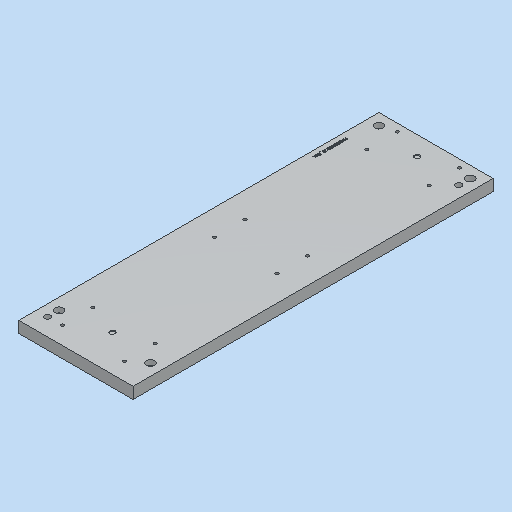
# Autodesk Inventor part: MM0948AN120_G01_109
Saved by Autodesk Inventor 2023.3 (Build 273359000, 359)
## iProperties
Part Number: MM0948AN120_G01_109
Material: 3.3547 AlMg4,5Mn0,7 - AW 5083
Description: =<RBPARTNOTITLE2>
Document SubType Name: Modeling
Designer: ric7an
Mass: 2852.53 g
Surface Area: 1646.02 cm^2
Volume: 1056.49 cm^3
Density: 2.7 g/cm^3
Appearance: Aluminium AnP
Created: 2023-03-23
RBDOCUMENTTYPE: DRF
RBDOCUMENTVERSION: 00
RBDRAWINGMAINSCALE: 1:1
RBDRAWINGMISSINGSPEC: --
RBDRAWINGVOLUME: --
RBGBEDGESIN1: +0,5
RBGBEDGESIN2: +0,2
RBGBEDGESOUT1: -0,3
RBGBEDGESOUT2: -0,1
RBMATERIAL: =<Material>
RBMATMEETS: --
RBMATNO: =<Part Number>
RBPARTMADEOF: 15 x 473 x 150 (FM)
RBPARTNO: SIEHE MNR
RBPARTNOTITLE1: manufactured part
RBPARTNOTITLE2: Anfertigungsteil
RBPARTSAFETYINDICATOR: --
RBSURFACE: anodised colourless
RBSURFACE2: eloxiert farblos
RBZEDGESNORM: ISO13715:2002-06
RBZGENDIMCLASS: m
RBZGENDIMNORM: ISO 2768-1:1989-11
RBZGENGEOCLASS: H
RBZGENGEONORM: ISO 2768-2:1989-11
RBZSURFACENORM: ISO13D2:2002-02
RBZTOLERANCENORM: ISO 14405-1:2010-12
AnP_Material: =<Material>
AnP_TemplVers: 20190222
AnP_Kategorie: 1
MaxAbmaße: 15 x 473 x 150 (FM)
AnP_Kommentar_aktuell: =<Comments>
AnP_Material_aktuell: =<Material>
Author: FH/Wi
Keywords: =<RBPARTMADEOF>
Comments: =<RBSURFACE2>
Revision Number: 01
Autodesk Inventor part; units mm, degrees
ref_plane "YZ Plane" through (0, 0, 0) normal (1, 0, 0) x (0, 1, 0)
ref_plane "XZ Plane" through (0, 0, 0) normal (0, 1, 0) x (-1, 0, 0)
ref_plane "XY Plane" through (0, 0, 0) normal (0, 0, 1) x (1, 0, 0)
sketch "Skizze1" plane through (0, 0, 0) normal (0, 0, 1) x (1, 0, 0)
  line L0 (-75, 236.5) -> (75, 236.5)
  line L1 (75, 236.5) -> (75, -236.5)
  line L2 (75, -236.5) -> (-75, -236.5)
  line L3 (-75, -236.5) -> (-75, 236.5)
  line L4 (0, 381.5) -> (0, -364) projected
  line L5 (-105, 0) -> (105, 0) projected
  point P0 (0, 0)
  dimension "d0" = 473
  dimension "d1" = 150
  constraints: 8 end point, 2 parallel, 1 horizontal, 1 perpendicular, 2 other
  measures "d0" distance of L0.end L1.end
  measures "d1" distance of L0.start L0.end
extrude "Extrusion1" add sketch "Skizze1" along normal blind 15
sketch "Skizze12" plane through (0, 0, 15) normal (0, 0, 1) x (1, 0, 0)
  line L0 (75, 236.5) -> (-75, 236.5) projected
  line L1 (-75, 236.5) -> (-75, -236.5) projected
  line L2 (75, -236.5) -> (75, 236.5) projected
  line L3 (-75, 236.5) -> (75, 236.5)
  line L4 (75, 236.5) -> (75, 156.5)
  line L5 (75, 156.5) -> (-75, 156.5)
  line L6 (-75, 156.5) -> (-75, 236.5)
  point P0 (0, 0)
  dimension "d107" = 80
  constraints: 8 end point, 2 parallel, 1 horizontal, 1 perpendicular, 1 point on line
  measures "d107" distance between parallel lines of L5 L0
sketch "Skizze2" plane through (0, 0, 15) normal (0, 0, 1) x (1, 0, 0)
  line L0 (0, 381.5) -> (0, -364) projected
  line L1 (-105, 0) -> (105, 0) projected
  line L2 (75, 236.5) -> (-75, 236.5) projected
  line L3 (-75, -236.5) -> (75, -236.5) projected
  point P0 (0, 0)
  point P1 (0, 211.5)
  point P2 (0, -188.5)
  dimension "d4" = 400
  dimension "d129" = 25
  dimension "d130" = 48
  constraints: 2 point on line
  measures "d4" distance of point (0, -188.5) point (0, 211.5)
  measures "d129" distance from line of point (0, 211.5) L2
  measures "d130" distance from line of L3 point (0, -188.5)
hole "Bohrung1" at (0, 211.5, 15) at (0, -188.5, 15) direction (0, 0, -1) diameter 7 depth 1.6
sketch "Skizze3" plane through (0, 0, 15) normal (0, 0, 1) x (1, 0, 0)
  line L0 (0, 381.5) -> (0, -364) projected
  line L1 (-105, 0) -> (105, 0) projected
  line L2 (75, 236.5) -> (-75, 236.5) projected
  point P0 (0, 0)
  point P1 (-41, 226.5)
  point P2 (-41, 186.5)
  point P3 (41, 226.5)
  point P4 (41, 186.5)
  dimension "d12" = 40
  dimension "d13" = 82
  dimension "d14" = 10
  constraints: 2 symmetric about line, 1 vertical alignment
  measures "d12" distance of point (41, 226.5) point (41, 186.5)
  measures "d13" distance of point (41, 226.5) point (-41, 226.5)
  measures "d14" distance from line of L2 point (-41, 226.5)
hole "Bohrung2" at (-41, 226.5, 15) at (-41, 186.5, 15) at (41, 226.5, 15) at (41, 186.5, 15) direction (0, 0, -1) diameter 4.134 end through all thread size "M5x0.8" designation "M5" class "6H" standard "ISO Metric profile"
pattern_linear "Rechteckige Anordnung1" count 3 spacing 200 along (0, -1, 0) of "Bohrung2"
sketch "Skizze6" plane through (0, 0, 15) normal (0, 0, -1) x (-1, 0, 0)
  line L0 (0, -364) -> (0, 381.5) projected
  line L1 (-105, 0) -> (105, 0) projected
  line L2 (75, 236.5) -> (-75, 236.5) projected
  line L3 (75, -236.5) -> (-75, -236.5) projected
  point P0 (0, 0)
  point P1 (-60, 221.5)
  point P2 (60, 221.5)
  point P3 (-60, -198.5)
  point P4 (60, -198.5)
  dimension "d48" = 120
  dimension "d85" = 420
  dimension "d86" = 120
  dimension "d104" = 38
  constraints: 2 symmetric about line, 1 horizontal alignment
  measures "d48" distance of point (60, 221.5) point (-60, 221.5)
  measures "d85" vertical distance of point (-60, -198.5) point (60, 221.5)
  measures "d86" distance of point (60, -198.5) point (-60, -198.5)
  measures "d104" distance from line of L3 point (-60, -198.5)
hole "Bohrung5" at (60, -198.5, 15) at (-60, -198.5, 15) at (60, 221.5, 15) at (-60, 221.5, 15) direction (0, 0, -1) diameter 6.6 end through all counterbore diameter 11 counterbore depth 6.8 clearance for "Inbusschraube ISO 4762  versenkt" size "M6" standard "ISO"
sketch "Skizze10" plane through (0, 0, 15) normal (0, 0, 1) x (1, 0, 0)
  circle A0 centre (-60, -198.5) radius 5.5 projected
  line L0 (-105, 0) -> (105, 0) projected
  line L1 (0, 381.5) -> (0, -364) projected
  circle A1 centre (-60, 221.5) radius 5.5 projected
  circle A2 centre (60, 221.5) radius 3.3 projected
  point P0 (0, 0)
  point P1 (-60, -213.5)
  point P2 (60, 206.5)
  dimension "d106" = 15
  dimension "d128" = 15
  constraints: 2 vertical alignment
  measures "d106" distance of point (-60, -213.5) A0.centre
  measures "d128" distance of point (60, 206.5) A2.centre
hole "Bohrung8" at (-60, -213.5, 15) at (60, 206.5, 15) direction (0, 0, -1) diameter 8 end through all
sketch "Skizze15" plane through (0, 0, 15) normal (0, 0, 1) x (1, 0, 0)
  line L0 (-65, 186.5) -> (-65, 138.8519) construction
  line L1 (-65, 138.8519) -> (-74.8862, 138.8519) construction
  line L2 (-74.8862, 138.8519) -> (-74.8862, 186.5) construction
  line L3 (-74.8862, 186.5) -> (-65, 186.5) construction
  line L4 (-75, 236.5) -> (-75, -236.5) projected
  line L5 (75, 236.5) -> (-75, 236.5) projected
  line L6 (-68.5794, 183.1447) -> (-68.5794, 183.6098)
  line L7 (-68.5794, 183.6098) -> (-65.5644, 183.6098)
  line L8 (-65.5644, 183.6098) -> (-67.6151, 184.5231)
  line L9 (-67.6151, 184.5231) -> (-67.6151, 184.8067)
  line L10 (-67.6151, 184.8067) -> (-65.5644, 185.7115)
  line L11 (-65.5644, 185.7115) -> (-68.5794, 185.7115)
  line L12 (-68.5794, 185.7115) -> (-68.5794, 186.1455)
  line L13 (-68.5794, 186.1455) -> (-65.0794, 186.1455)
  line L14 (-65.0794, 186.1455) -> (-65.0794, 185.5101)
  line L15 (-65.0794, 185.5101) -> (-67.028, 184.6365)
  line L16 (-67.028, 184.6365) -> (-65.0794, 183.7913)
  line L17 (-65.0794, 183.7913) -> (-65.0794, 183.1447)
  line L18 (-65.0794, 183.1447) -> (-68.5794, 183.1447)
  line L19 (-68.5794, 179.4348) -> (-68.5794, 179.8999)
  line L20 (-68.5794, 179.8999) -> (-65.5644, 179.8999)
  line L21 (-65.5644, 179.8999) -> (-67.6151, 180.8132)
  line L22 (-67.6151, 180.8132) -> (-67.6151, 181.0968)
  line L23 (-67.6151, 181.0968) -> (-65.5644, 182.0016)
  line L24 (-65.5644, 182.0016) -> (-68.5794, 182.0016)
  line L25 (-68.5794, 182.0016) -> (-68.5794, 182.4356)
  line L26 (-68.5794, 182.4356) -> (-65.0794, 182.4356)
  line L27 (-65.0794, 182.4356) -> (-65.0794, 181.8002)
  line L28 (-65.0794, 181.8002) -> (-67.028, 180.9267)
  line L29 (-67.028, 180.9267) -> (-65.0794, 180.0814)
  line L30 (-65.0794, 180.0814) -> (-65.0794, 179.4348)
  line L31 (-65.0794, 179.4348) -> (-68.5794, 179.4348)
  spline S0 degree 2 poles (-66.8294, 176.6467) (-67.7711, 176.6467) (-68.6532, 177.1941) (-68.6532, 177.7642) knots 0 0 0 1 2 2 2
  spline S1 degree 2 poles (-68.6532, 177.7642) (-68.6532, 178.3428) (-67.7541, 178.8845) (-66.8323, 178.8845) knots 0 0 0 1 2 2 2
  spline S2 degree 2 poles (-66.8323, 178.8845) (-65.8849, 178.8845) (-65.0085, 178.3371) (-65.0085, 177.7642) knots 0 0 0 1 2 2 2
  spline S3 degree 2 poles (-65.0085, 177.7642) (-65.0085, 177.1884) (-65.9161, 176.6467) (-66.8294, 176.6467) knots 0 0 0 1 2 2 2
  spline S4 degree 2 poles (-67.8959, 177.248) (-67.7229, 177.1799) (-67.1896, 177.1232) (-66.8294, 177.1232) knots 0 0 0 1 2 2 2
  spline S5 degree 2 poles (-66.8294, 177.1232) (-66.4692, 177.1232) (-65.9388, 177.1799) (-65.7601, 177.2508) knots 0 0 0 1 2 2 2
  spline S6 degree 2 poles (-65.7601, 177.2508) (-65.5814, 177.3217) (-65.3971, 177.5685) (-65.3971, 177.7642) knots 0 0 0 1 2 2 2
  spline S7 degree 2 poles (-65.3971, 177.7642) (-65.3971, 177.9599) (-65.5814, 178.2123) (-65.7658, 178.2861) knots 0 0 0 1 2 2 2
  spline S8 degree 2 poles (-65.7658, 178.2861) (-65.9445, 178.357) (-66.4891, 178.408) (-66.8323, 178.408) knots 0 0 0 1 2 2 2
  spline S9 degree 2 poles (-66.8323, 178.408) (-67.201, 178.408) (-67.6945, 178.3626) (-67.8874, 178.2889) knots 0 0 0 1 2 2 2
  spline S10 degree 2 poles (-67.8874, 178.2889) (-68.0689, 178.2208) (-68.2646, 177.9684) (-68.2646, 177.7642) knots 0 0 0 1 2 2 2
  spline S11 degree 2 poles (-68.2646, 177.7642) (-68.2646, 177.5713) (-68.0802, 177.3189) (-67.8959, 177.248) knots 0 0 0 1 2 2 2
  spline S12 degree 2 poles (-66.2168, 176.295) (-65.9473, 176.295) (-65.4992, 176.1191) (-65.3375, 175.966) knots 0 0 0 1 2 2 2
  spline S13 degree 2 poles (-65.3375, 175.966) (-65.1815, 175.8213) (-65.0085, 175.3987) (-65.0085, 175.1831) knots 0 0 0 1 2 2 2
  spline S14 degree 2 poles (-65.0085, 175.1831) (-65.0085, 174.9421) (-65.1702, 174.5506) (-65.3233, 174.406) knots 0 0 0 1 2 2 2
  spline S15 degree 2 poles (-65.3233, 174.406) (-65.5162, 174.2245) (-66.1402, 174.0259) (-66.6195, 174.0259) knots 0 0 0 1 2 2 2
  spline S16 degree 2 poles (-66.6195, 174.0259) (-67.0535, 174.0259) (-67.8306, 174.2216) (-68.0887, 174.4117) knots 0 0 0 1 2 2 2
  spline S17 degree 2 poles (-68.0887, 174.4117) (-68.361, 174.613) (-68.6475, 175.1803) (-68.6475, 175.5944) knots 0 0 0 1 2 2 2
  spline S18 degree 2 poles (-68.6475, 175.5944) (-68.6475, 175.688) (-68.6276, 175.9007) (-68.5993, 175.9915) knots 0 0 0 1 2 2 2
  line L32 (-68.5993, 175.9915) -> (-68.1483, 175.9915)
  line L33 (-68.1483, 175.9915) -> (-68.1483, 175.9688)
  spline S19 degree 2 poles (-68.1483, 175.9688) (-68.1823, 175.9092) (-68.2419, 175.6596) (-68.2419, 175.532) knots 0 0 0 1 2 2 2
  spline S20 degree 2 poles (-68.2419, 175.532) (-68.2419, 175.0725) (-67.6349, 174.5478) (-67.0733, 174.5109) knots 0 0 0 1 2 2 2
  spline S21 degree 2 poles (-67.0733, 174.5109) (-67.201, 174.6981) (-67.3173, 175.0385) (-67.3173, 175.2399) knots 0 0 0 1 2 2 2
  spline S22 degree 2 poles (-67.3173, 175.2399) (-67.3173, 175.4327) (-67.2322, 175.7532) (-67.1102, 175.9149) knots 0 0 0 1 2 2 2
  spline S23 degree 2 poles (-67.1102, 175.9149) (-66.9656, 176.1021) (-66.5259, 176.295) (-66.2168, 176.295) knots 0 0 0 1 2 2 2
  spline S24 degree 2 poles (-66.5146, 174.4996) (-66.16, 174.4996) (-65.7119, 174.6301) (-65.59, 174.7464) knots 0 0 0 1 2 2 2
  spline S25 degree 2 poles (-65.59, 174.7464) (-65.4765, 174.8485) (-65.3914, 175.0612) (-65.3914, 175.186) knots 0 0 0 1 2 2 2
  spline S26 degree 2 poles (-65.3914, 175.186) (-65.3914, 175.4753) (-65.8055, 175.8185) (-66.1969, 175.8185) knots 0 0 0 1 2 2 2
  spline S27 degree 2 poles (-66.1969, 175.8185) (-66.4182, 175.8185) (-66.7046, 175.705) (-66.8067, 175.5802) knots 0 0 0 1 2 2 2
  spline S28 degree 2 poles (-66.8067, 175.5802) (-66.8805, 175.4895) (-66.9287, 175.2654) (-66.9287, 175.1349) knots 0 0 0 1 2 2 2
  spline S29 degree 2 poles (-66.9287, 175.1349) (-66.9287, 174.9846) (-66.8237, 174.6386) (-66.7358, 174.5081) knots 0 0 0 1 2 2 2
  spline S30 degree 2 poles (-66.7358, 174.5081) (-66.7018, 174.5053) (-66.5855, 174.4996) (-66.5146, 174.4996) knots 0 0 0 1 2 2 2
  line L34 (-67.3768, 171.3201) -> (-67.3768, 171.737)
  line L35 (-67.3768, 171.737) -> (-68.5794, 171.737)
  line L36 (-68.5794, 171.737) -> (-68.5794, 172.188)
  line L37 (-68.5794, 172.188) -> (-67.3768, 172.188)
  line L38 (-67.3768, 172.188) -> (-67.3768, 173.7338)
  line L39 (-67.3768, 173.7338) -> (-66.8833, 173.7338)
  line L40 (-66.8833, 173.7338) -> (-65.0794, 172.1682)
  line L41 (-65.0794, 172.1682) -> (-65.0794, 171.737)
  line L42 (-65.0794, 171.737) -> (-66.9996, 171.737)
  line L43 (-66.9996, 171.737) -> (-66.9996, 171.3201)
  line L44 (-66.9996, 171.3201) -> (-67.3768, 171.3201)
  line L45 (-66.9996, 172.188) -> (-65.6325, 172.188)
  line L46 (-65.6325, 172.188) -> (-66.9996, 173.3651)
  line L47 (-66.9996, 173.3651) -> (-66.9996, 172.188)
  spline S31 degree 2 poles (-68.6588, 169.8878) (-68.6588, 170.1487) (-68.5028, 170.577) (-68.3582, 170.7273) knots 0 0 0 1 2 2 2
  spline S32 degree 2 poles (-68.3582, 170.7273) (-68.2164, 170.8748) (-67.8306, 171.028) (-67.6122, 171.028) knots 0 0 0 1 2 2 2
  spline S33 degree 2 poles (-67.6122, 171.028) (-67.3286, 171.028) (-66.8521, 170.7245) (-66.7103, 170.4352) knots 0 0 0 1 2 2 2
  line L48 (-66.7103, 170.4352) -> (-66.6961, 170.4352)
  spline S34 degree 2 poles (-66.6961, 170.4352) (-66.5458, 170.6933) (-66.1884, 170.9429) (-65.9218, 170.9429) knots 0 0 0 1 2 2 2
  spline S35 degree 2 poles (-65.9218, 170.9429) (-65.5276, 170.9429) (-65, 170.3472) (-65, 169.8878) knots 0 0 0 1 2 2 2
  spline S36 degree 2 poles (-65, 169.8878) (-65, 169.4113) (-65.4992, 168.8355) (-65.8906, 168.8355) knots 0 0 0 1 2 2 2
  spline S37 degree 2 poles (-65.8906, 168.8355) (-66.126, 168.8355) (-66.5855, 169.1106) (-66.716, 169.3687) knots 0 0 0 1 2 2 2
  line L49 (-66.716, 169.3687) -> (-66.7301, 169.3687)
  spline S38 degree 2 poles (-66.7301, 169.3687) (-66.872, 169.0624) (-67.2804, 168.7476) (-67.6037, 168.7476) knots 0 0 0 1 2 2 2
  spline S39 degree 2 poles (-67.6037, 168.7476) (-68.0519, 168.7476) (-68.6588, 169.3999) (-68.6588, 169.8878) knots 0 0 0 1 2 2 2
  spline S40 degree 2 poles (-67.6491, 169.2297) (-67.4335, 169.2297) (-67.1783, 169.3999) (-67.0478, 169.641) knots 0 0 0 1 2 2 2
  spline S41 degree 2 poles (-67.0478, 169.641) (-67.0024, 169.7204) (-66.8975, 169.987) (-66.8294, 170.1544) knots 0 0 0 1 2 2 2
  spline S42 degree 2 poles (-66.8294, 170.1544) (-66.9571, 170.3472) (-67.3371, 170.5543) (-67.5782, 170.5543) knots 0 0 0 1 2 2 2
  spline S43 degree 2 poles (-67.5782, 170.5543) (-67.8959, 170.5543) (-68.31, 170.1714) (-68.31, 169.8821) knots 0 0 0 1 2 2 2
  spline S44 degree 2 poles (-68.31, 169.8821) (-68.31, 169.5871) (-67.9554, 169.2297) (-67.6491, 169.2297) knots 0 0 0 1 2 2 2
  spline S45 degree 2 poles (-65.8963, 169.295) (-65.6609, 169.295) (-65.346, 169.6098) (-65.346, 169.8906) knots 0 0 0 1 2 2 2
  spline S46 degree 2 poles (-65.346, 169.8906) (-65.346, 170.1459) (-65.6268, 170.472) (-65.8679, 170.472) knots 0 0 0 1 2 2 2
  spline S47 degree 2 poles (-65.8679, 170.472) (-66.0409, 170.472) (-66.282, 170.3047) (-66.3784, 170.1374) knots 0 0 0 1 2 2 2
  spline S48 degree 2 poles (-66.3784, 170.1374) (-66.4182, 170.0665) (-66.5571, 169.7658) (-66.5968, 169.6438) knots 0 0 0 1 2 2 2
  spline S49 degree 2 poles (-66.5968, 169.6438) (-66.4408, 169.4396) (-66.109, 169.295) (-65.8963, 169.295) knots 0 0 0 1 2 2 2
  line L50 (-68.5794, 168.5972) -> (-65.0794, 167.4173)
  line L51 (-65.0794, 167.4173) -> (-65.0794, 166.8444)
  line L52 (-65.0794, 166.8444) -> (-68.5794, 165.6645)
  line L53 (-68.5794, 165.6645) -> (-68.5794, 166.1552)
  line L54 (-68.5794, 166.1552) -> (-67.6009, 166.4729)
  line L55 (-67.6009, 166.4729) -> (-67.6009, 167.8088)
  line L56 (-67.6009, 167.8088) -> (-68.5794, 168.1264)
  line L57 (-68.5794, 168.1264) -> (-68.5794, 168.5972)
  line L58 (-67.2038, 166.6005) -> (-65.5559, 167.1422)
  line L59 (-65.5559, 167.1422) -> (-67.2038, 167.6811)
  line L60 (-67.2038, 167.6811) -> (-67.2038, 166.6005)
  line L61 (-68.5794, 162.8282) -> (-68.5794, 163.3501)
  line L62 (-68.5794, 163.3501) -> (-65.5616, 164.8987)
  line L63 (-65.5616, 164.8987) -> (-68.5794, 164.8987)
  line L64 (-68.5794, 164.8987) -> (-68.5794, 165.3327)
  line L65 (-68.5794, 165.3327) -> (-65.0794, 165.3327)
  line L66 (-65.0794, 165.3327) -> (-65.0794, 164.6718)
  line L67 (-65.0794, 164.6718) -> (-67.8505, 163.2622)
  line L68 (-67.8505, 163.2622) -> (-65.0794, 163.2622)
  line L69 (-65.0794, 163.2622) -> (-65.0794, 162.8282)
  line L70 (-65.0794, 162.8282) -> (-68.5794, 162.8282)
  line L71 (-68.5794, 160.2358) -> (-68.5794, 161.9433)
  line L72 (-68.5794, 161.9433) -> (-68.222, 161.9433)
  line L73 (-68.222, 161.9433) -> (-68.222, 161.3079)
  line L74 (-68.222, 161.3079) -> (-65.8764, 161.3079)
  line L75 (-65.8764, 161.3079) -> (-65.8764, 161.9433)
  line L76 (-65.8764, 161.9433) -> (-65.5559, 161.9433)
  spline S50 degree 2 poles (-65.5559, 161.9433) (-65.5559, 161.5831) (-65.3517, 161.2427) (-65.0681, 161.22) knots 0 0 0 1 2 2 2
  line L77 (-65.0681, 161.22) -> (-65.0681, 160.857)
  line L78 (-65.0681, 160.857) -> (-68.222, 160.857)
  line L79 (-68.222, 160.857) -> (-68.222, 160.2358)
  line L80 (-68.222, 160.2358) -> (-68.5794, 160.2358)
  line L81 (-68.5794, 157.4335) -> (-68.5794, 159.592)
  line L82 (-68.5794, 159.592) -> (-68.0831, 159.592)
  spline S51 degree 2 poles (-68.0831, 159.592) (-67.8647, 159.3594) (-67.4591, 158.9453) (-67.2407, 158.7468) knots 0 0 0 1 2 2 2
  spline S52 degree 2 poles (-67.2407, 158.7468) (-66.8011, 158.3468) (-66.2735, 158.0547) (-65.9927, 158.0547) knots 0 0 0 1 2 2 2
  spline S53 degree 2 poles (-65.9927, 158.0547) (-65.8452, 158.0547) (-65.624, 158.1455) (-65.5531, 158.2277) knots 0 0 0 1 2 2 2
  spline S54 degree 2 poles (-65.5531, 158.2277) (-65.4822, 158.31) (-65.4113, 158.5255) (-65.4113, 158.656) knots 0 0 0 1 2 2 2
  spline S55 degree 2 poles (-65.4113, 158.656) (-65.4113, 158.7808) (-65.4737, 159.0361) (-65.5219, 159.1524) knots 0 0 0 1 2 2 2
  spline S56 degree 2 poles (-65.5219, 159.1524) (-65.5616, 159.2516) (-65.675, 159.436) (-65.7147, 159.4927) knots 0 0 0 1 2 2 2
  line L83 (-65.7147, 159.4927) -> (-65.7147, 159.5182)
  line L84 (-65.7147, 159.5182) -> (-65.2156, 159.5182)
  spline S57 degree 2 poles (-65.2156, 159.5182) (-65.1447, 159.3736) (-65.0057, 158.8545) (-65.0057, 158.622) knots 0 0 0 1 2 2 2
  spline S58 degree 2 poles (-65.0057, 158.622) (-65.0057, 158.1313) (-65.5247, 157.5782) (-65.9672, 157.5782) knots 0 0 0 1 2 2 2
  spline S59 degree 2 poles (-65.9672, 157.5782) (-66.1742, 157.5782) (-66.5203, 157.6746) (-66.6677, 157.7597) knots 0 0 0 1 2 2 2
  spline S60 degree 2 poles (-66.6677, 157.7597) (-66.8209, 157.8448) (-67.1216, 158.0916) (-67.2662, 158.2277) knots 0 0 0 1 2 2 2
  spline S61 degree 2 poles (-67.2662, 158.2277) (-67.5073, 158.4489) (-68.0235, 158.9907) (-68.1738, 159.1524) knots 0 0 0 1 2 2 2
  line L85 (-68.1738, 159.1524) -> (-68.1738, 157.4335)
  line L86 (-68.1738, 157.4335) -> (-68.5794, 157.4335)
  spline S62 degree 2 poles (-66.8294, 154.7873) (-67.7711, 154.7873) (-68.6532, 155.3347) (-68.6532, 155.9048) knots 0 0 0 1 2 2 2
  spline S63 degree 2 poles (-68.6532, 155.9048) (-68.6532, 156.4834) (-67.7541, 157.0251) (-66.8323, 157.0251) knots 0 0 0 1 2 2 2
  spline S64 degree 2 poles (-66.8323, 157.0251) (-65.8849, 157.0251) (-65.0085, 156.4777) (-65.0085, 155.9048) knots 0 0 0 1 2 2 2
  spline S65 degree 2 poles (-65.0085, 155.9048) (-65.0085, 155.329) (-65.9161, 154.7873) (-66.8294, 154.7873) knots 0 0 0 1 2 2 2
  spline S66 degree 2 poles (-67.8959, 155.3886) (-67.7229, 155.3205) (-67.1896, 155.2638) (-66.8294, 155.2638) knots 0 0 0 1 2 2 2
  spline S67 degree 2 poles (-66.8294, 155.2638) (-66.4692, 155.2638) (-65.9388, 155.3205) (-65.7601, 155.3914) knots 0 0 0 1 2 2 2
  spline S68 degree 2 poles (-65.7601, 155.3914) (-65.5814, 155.4623) (-65.3971, 155.7091) (-65.3971, 155.9048) knots 0 0 0 1 2 2 2
  spline S69 degree 2 poles (-65.3971, 155.9048) (-65.3971, 156.1005) (-65.5814, 156.3529) (-65.7658, 156.4267) knots 0 0 0 1 2 2 2
  spline S70 degree 2 poles (-65.7658, 156.4267) (-65.9445, 156.4976) (-66.4891, 156.5486) (-66.8323, 156.5486) knots 0 0 0 1 2 2 2
  spline S71 degree 2 poles (-66.8323, 156.5486) (-67.201, 156.5486) (-67.6945, 156.5032) (-67.8874, 156.4295) knots 0 0 0 1 2 2 2
  spline S72 degree 2 poles (-67.8874, 156.4295) (-68.0689, 156.3614) (-68.2646, 156.109) (-68.2646, 155.9048) knots 0 0 0 1 2 2 2
  spline S73 degree 2 poles (-68.2646, 155.9048) (-68.2646, 155.7119) (-68.0802, 155.4595) (-67.8959, 155.3886) knots 0 0 0 1 2 2 2
  line L87 (-69.2828, 151.9311) -> (-69.2828, 154.6313)
  line L88 (-69.2828, 154.6313) -> (-68.9793, 154.6313)
  line L89 (-68.9793, 154.6313) -> (-68.9793, 151.9311)
  line L90 (-68.9793, 151.9311) -> (-69.2828, 151.9311)
  spline S74 degree 2 poles (-68.6475, 150.1471) (-68.6475, 150.5186) (-68.4206, 151.1341) (-68.1908, 151.3553) knots 0 0 0 1 2 2 2
  spline S75 degree 2 poles (-68.1908, 151.3553) (-67.9583, 151.5766) (-67.2719, 151.812) (-66.8266, 151.812) knots 0 0 0 1 2 2 2
  spline S76 degree 2 poles (-66.8266, 151.812) (-66.404, 151.812) (-65.7346, 151.5737) (-65.4964, 151.3525) knots 0 0 0 1 2 2 2
  spline S77 degree 2 poles (-65.4964, 151.3525) (-65.2666, 151.1398) (-65.017, 150.5158) (-65.017, 150.1442) knots 0 0 0 1 2 2 2
  spline S78 degree 2 poles (-65.017, 150.1442) (-65.017, 149.9656) (-65.0681, 149.6422) (-65.1135, 149.4947) knots 0 0 0 1 2 2 2
  spline S79 degree 2 poles (-65.1135, 149.4947) (-65.1475, 149.3756) (-65.2723, 149.0863) (-65.3177, 148.9984) knots 0 0 0 1 2 2 2
  line L91 (-65.3177, 148.9984) -> (-65.8793, 148.9984)
  line L92 (-65.8793, 148.9984) -> (-65.8793, 149.0381)
  spline S80 degree 2 poles (-65.8793, 149.0381) (-65.8027, 149.126) (-65.6637, 149.3104) (-65.5843, 149.4806) knots 0 0 0 1 2 2 2
  spline S81 degree 2 poles (-65.5843, 149.4806) (-65.5134, 149.6224) (-65.4198, 149.9883) (-65.4198, 150.1981) knots 0 0 0 1 2 2 2
  spline S82 degree 2 poles (-65.4198, 150.1981) (-65.4198, 150.703) (-66.1799, 151.327) (-66.8124, 151.327) knots 0 0 0 1 2 2 2
  spline S83 degree 2 poles (-66.8124, 151.327) (-67.1641, 151.327) (-67.6917, 151.1625) (-67.8732, 151.0065) knots 0 0 0 1 2 2 2
  spline S84 degree 2 poles (-67.8732, 151.0065) (-68.0547, 150.8562) (-68.2447, 150.4307) (-68.2447, 150.1641) knots 0 0 0 1 2 2 2
  spline S85 degree 2 poles (-68.2447, 150.1641) (-68.2447, 149.9684) (-68.188, 149.577) (-68.1313, 149.4437) knots 0 0 0 1 2 2 2
  line L93 (-68.1313, 149.4437) -> (-67.2265, 149.4437)
  line L94 (-67.2265, 149.4437) -> (-67.2265, 150.2549)
  line L95 (-67.2265, 150.2549) -> (-66.8181, 150.2549)
  line L96 (-66.8181, 150.2549) -> (-66.8181, 148.9842)
  line L97 (-66.8181, 148.9842) -> (-68.3468, 148.9842)
  spline S86 degree 2 poles (-68.3468, 148.9842) (-68.3865, 149.0721) (-68.5085, 149.3728) (-68.5454, 149.5004) knots 0 0 0 1 2 2 2
  spline S87 degree 2 poles (-68.5454, 149.5004) (-68.5964, 149.6734) (-68.6475, 149.9514) (-68.6475, 150.1471) knots 0 0 0 1 2 2 2
  line L98 (-68.5794, 145.9806) -> (-68.5794, 146.5138)
  line L99 (-68.5794, 146.5138) -> (-67.184, 147.3647)
  line L100 (-67.184, 147.3647) -> (-68.5794, 148.2326)
  line L101 (-68.5794, 148.2326) -> (-68.5794, 148.7346)
  line L102 (-68.5794, 148.7346) -> (-66.8266, 147.6199)
  line L103 (-66.8266, 147.6199) -> (-65.0794, 148.7006)
  line L104 (-65.0794, 148.7006) -> (-65.0794, 148.1673)
  line L105 (-65.0794, 148.1673) -> (-66.4494, 147.3335)
  line L106 (-66.4494, 147.3335) -> (-65.0794, 146.4826)
  line L107 (-65.0794, 146.4826) -> (-65.0794, 145.9806)
  line L108 (-65.0794, 145.9806) -> (-66.8039, 147.0754)
  line L109 (-66.8039, 147.0754) -> (-68.5794, 145.9806)
  line L110 (-68.5794, 143.1868) -> (-68.5794, 143.72)
  line L111 (-68.5794, 143.72) -> (-67.184, 144.5709)
  line L112 (-67.184, 144.5709) -> (-68.5794, 145.4388)
  line L113 (-68.5794, 145.4388) -> (-68.5794, 145.9408)
  line L114 (-68.5794, 145.9408) -> (-66.8266, 144.8262)
  line L115 (-66.8266, 144.8262) -> (-65.0794, 145.9068)
  line L116 (-65.0794, 145.9068) -> (-65.0794, 145.3736)
  line L117 (-65.0794, 145.3736) -> (-66.4494, 144.5397)
  line L118 (-66.4494, 144.5397) -> (-65.0794, 143.6888)
  line L119 (-65.0794, 143.6888) -> (-65.0794, 143.1868)
  line L120 (-65.0794, 143.1868) -> (-66.8039, 144.2816)
  line L121 (-66.8039, 144.2816) -> (-68.5794, 143.1868)
  point P0 (0, 0)
  dimension "d131" = 10
  dimension "d132" = 50
  constraints: 1 vertical, 2 other
  measures "d131" distance between parallel lines of L0 L4
  measures "d132" distance between parallel lines of L3 L5
emboss "Prägen1" sketch "Skizze15" operation cut depth 0.1 direction (0, 0, -1)
